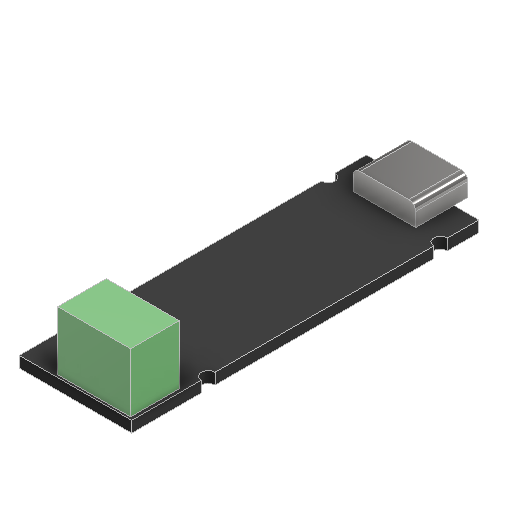
# Autodesk Inventor part: COTS_MKS_Cacable_1_0_PRO
Saved by Autodesk Inventor 2027 (Build 310192060, 192F)
## iProperties
Created: 2026-01-18
Part Number: COTS_MKS_Cacable_1_0_PRO
Material: Generic
Document SubType Name: Modeling
Designer: Andrzej
Density: 1 g/cm^3
Appearance: Rubber - Black
Author: Andrzej
Autodesk Inventor part; units mm, degrees
ref_plane "YZ Plane" through (0, 0, 0) normal (1, 0, 0) x (0, 1, 0)
ref_plane "XZ Plane" through (0, 0, 0) normal (0, 1, 0) x (-1, 0, 0)
ref_plane "XY Plane" through (0, 0, 0) normal (0, 0, 1) x (1, 0, 0)
sketch "Sketch1" plane through (0, 0, 0) normal (0, 1, 0) x (-1, 0, 0)
  line L0 (8.1, 25) -> (-8.1, 25)
  line L1 (-8.1, 25) -> (-8.1, -25)
  line L2 (-8.1, -25) -> (8.1, -25)
  line L3 (8.1, -25) -> (8.1, 25)
  circle A0 centre (8.1, 14) radius 1
  circle A1 centre (-8.1, 14) radius 1
  circle A2 centre (-8.1, -19.5) radius 1
  circle A3 centre (8.1, -19.5) radius 1
  point P0 (0, 0)
  point P1 (-8.1, 15)
  point P2 (-8.1, 13)
  point P3 (-8.1, -18.5)
  point P4 (-8.1, -20.5)
  point P5 (8.1, -20.5)
  point P6 (8.1, -18.5)
  point P7 (8.1, 13)
  point P8 (8.1, 15)
  dimension "d0" = 50
  dimension "d1" = 16.2
  dimension "d2" = 8.1
  dimension "d3" = 25
  dimension "d4" = 11
  dimension "d6" = 2
  dimension "d7" = 2
  dimension "d8" = 5.5
  dimension "d9" = 5.5
  dimension "d10" = 2
  dimension "d11" = 2
  constraints: 8 end point, 4 centre point, 4 coincident, 4 point on line, 2 parallel, 1 horizontal, 1 horizontal alignment, 1 perpendicular
  measures "d0" distance of L2.end L0.start
  measures "d1" distance of L0.start L0.end
  measures "d2" distance from line of point (0, 0) L3
  measures "d3" distance from line of L0 point (0, 0)
  measures "d4" distance from line of point (8.1, 14) L0
  measures "d6" diameter of A0
  measures "d7" diameter of A1
  measures "d8" distance from line of L2 point (8.1, -19.5)
  measures "d9" distance from line of L2 point (-8.1, -19.5)
  measures "d10" diameter of A2
  measures "d11" diameter of A3
extrude "Extrusion1" add sketch "Sketch1" along normal blind 1.6 contours L3 A0 A3 L2 L1 A2 A1 L0
sketch "Sketch2" plane through (0, 1.6, 0) normal (0, 1, 0) x (1, 0, 0)
  line L0 (8.1, -25) -> (8.1, -15) projected
  line L1 (7.5844, -24.6468) -> (-2.9156, -24.6468)
  line L2 (-2.9156, -24.6468) -> (-2.9156, -17.6468)
  line L3 (-2.9156, -17.6468) -> (7.5844, -17.6468)
  line L4 (7.5844, -17.6468) -> (7.5844, -24.6468)
  point P0 (0, 0)
  dimension "d18" = 10.5
  dimension "d19" = 7
  constraints: 8 end point, 2 parallel, 1 horizontal, 1 perpendicular
  measures "d18" distance of L2.end L3.end
  measures "d19" distance of L1.end L2.end
extrude "Extrusion2" add sketch "Sketch2" along normal blind 8.5
sketch "Sketch3" plane through (0, 1.6, 0) normal (0, 1, 0) x (1, 0, 0)
  line L0 (-4.5, 19.5) -> (4.5, 19.5)
  line L1 (4.5, 19.5) -> (4.5, 27)
  line L2 (4.5, 27) -> (-4.5, 27)
  line L3 (-4.5, 27) -> (-4.5, 19.5)
  line L4 (8.1, 25) -> (-8.1, 25) projected
  point P0 (0, 0)
  dimension "d20" = 9
  dimension "d21" = 7.5
  dimension "d22" = 4.5
  dimension "d23" = 2
  constraints: 8 end point, 2 parallel, 1 horizontal, 1 perpendicular
  measures "d20" distance of L2.end L1.end
  measures "d21" distance of L1.end L0.end
  measures "d22" distance from line of point (0, 0) L3
  measures "d23" distance between parallel lines of L4 L2
extrude "Extrusion3" add sketch "Sketch3" along normal blind 3
fillet "Fillet1" radius 1 2 edges at (4.5, 4.6, -23.25) (-4.5, 4.6, -23.25)
equation "\"d2\" = 0.5 * d1"
equation "\"d3\" = 0.5 * d0"
equation "\"d9\" = d8"
equation "\"d22\" = 0.5 * d20"
body "Solid1"
